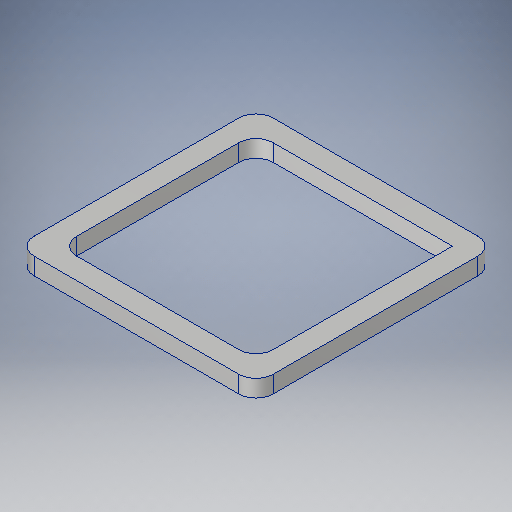
# Autodesk Inventor part: BT017_thutrn22_26
Saved by Autodesk Inventor 2025.3 (Build 293356000, 356)
## iProperties
Company: HTBLA Kaindorf
RuleStatus: InUse
Created: 2026-08-14
Part Number: BT017_thutrn22_26
Project: Biegeroboter
Material: Aluminium 6061
Description: gehäuse_oben
Document SubType Name: Modeling
Designer: thutrn22
Density: 2.7 g/cm^3
Appearance: Aluminium - flach
Mass: 171.546 g
Surface Area: 226.066 cm^2
Volume: 63.5354 cm^3
AfterDocNew0: iProperties-Editor_aufrufen
Author: trist
Keywords: 2026
Autodesk Inventor part; units mm, degrees
ref_plane "YZ Plane" through (0, 0, 0) normal (1, 0, 0) x (0, 1, 0)
ref_plane "XZ Plane" through (0, 0, 0) normal (0, 1, 0) x (-1, 0, 0)
ref_plane "XY Plane" through (0, 0, 0) normal (0, 0, 1) x (1, 0, 0)
sketch "Skizze4" plane through (0, 0, 0) normal (0, 0, 1) x (1, 0, 0)
  line L0 (-100.8995, 0) -> (100.8995, 0) projected
  line L1 (0, -100.8995) -> (0, 100.8995) projected
  line L2 (-60, 70) -> (60, 70)
  line L3 (70, 60) -> (70, -60)
  line L4 (60, -70) -> (-60, -70)
  line L5 (-70, -60) -> (-70, 60)
  line L6 (-57.5, 57.5) -> (47.5, 57.5)
  line L7 (57.5, 47.5) -> (57.5, -47.5)
  line L8 (47.5, -57.5) -> (-47.5, -57.5)
  line L9 (-57.5, -47.5) -> (-57.5, 57.5)
  arc A0 (-60, 70) -> (-70, 60) centre (-60, 60) ccw
  arc A1 (70, 60) -> (60, 70) centre (60, 60) ccw
  arc A2 (60, -70) -> (70, -60) centre (60, -60) ccw
  arc A3 (-70, -60) -> (-60, -70) centre (-60, -60) ccw
  arc A4 (-57.5, -47.5) -> (-47.5, -57.5) centre (-47.5, -47.5) ccw
  arc A5 (47.5, -57.5) -> (57.5, -47.5) centre (47.5, -47.5) ccw
  arc A6 (57.5, 47.5) -> (47.5, 57.5) centre (47.5, 47.5) ccw
  point P0 (0, 0)
  point P1 (70, -70)
  point P2 (70, 70)
  point P3 (-70, -70)
  dimension "d10" = 140
  dimension "d11" = 140
  dimension "d12" = 12.5
  dimension "d13" = 12.5
  dimension "d14" = 12.5
  dimension "d15" = 12.5
  dimension "d16" = 10
  constraints: 16 end point, 14 point on circle, 14 tangent, 7 centre point, 6 equal radius, 6 point on line, 4 parallel, 2 horizontal, 2 perpendicular, 2 other
  measures "d10" distance of point (70, -70) point (-70, -70)
  measures "d11" distance of point (70, 70) point (70, -70)
  measures "d12" distance between parallel lines of L4 L8
  measures "d13" distance between parallel lines of L3 L7
  measures "d14" distance between parallel lines of L2 L6
  measures "d15" distance between parallel lines of L5 L9
  measures "d16" radius of A0
extrude "Extrusion3" add sketch "Skizze4" along normal blind 10 contours L5 A0 L2 L1 L6 L9 L0 | L0 L9 A4 L8 L1 L4 A3 L5 | L7 A6 L6 L1 L2 A1 L3 L0 | L0 L3 A2 L4 L1 L8 A5 L7
